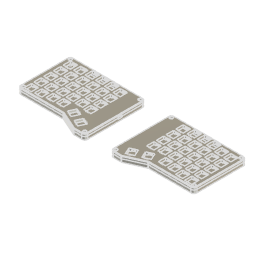
Dos60S (Autodesk Fusion 360 design; units mm, degrees)
Autodesk Fusion 360 part; units mm, degrees
(part 1 of 4)
sketch "Switch_Holes" plane through (0, 0, 0) normal (0, 0, 1) x (1, 0, 0) in component "Plate_Left"
  line L0 (2.5, -8.35) -> (16.5, -8.35)
  line L1 (16.5, -8.35) -> (16.5, -22.35)
  line L2 (16.5, -22.35) -> (2.5, -22.35)
  line L3 (2.5, -22.35) -> (2.5, -8.35)
  line L4 (2.5, -8.35) -> (16.5, -22.35) construction
  line L5 (2.5, -41.4) -> (2.5, -27.4)
  line L6 (2.5, -27.4) -> (16.5, -27.4)
  line L7 (2.5, -27.4) -> (16.5, -41.4) construction
  line L8 (16.5, -41.4) -> (2.5, -41.4)
  line L9 (16.5, -27.4) -> (16.5, -41.4)
  line L10 (9.5, -15.35) -> (9.5, -34.4) construction
  line L11 (16.5, -60.45) -> (2.5, -60.45)
  line L12 (16.5, -46.45) -> (16.5, -60.45)
  line L13 (2.5, -46.45) -> (16.5, -60.45) construction
  line L14 (2.5, -60.45) -> (2.5, -46.45)
  line L15 (2.5, -46.45) -> (16.5, -46.45)
  line L16 (16.5, -79.5) -> (2.5, -79.5)
  line L17 (16.5, -65.5) -> (16.5, -79.5)
  line L18 (2.5, -65.5) -> (16.5, -79.5) construction
  line L19 (2.5, -79.5) -> (2.5, -65.5)
  line L20 (2.5, -65.5) -> (16.5, -65.5)
  line L21 (16.5, -98.55) -> (2.5, -98.55)
  line L22 (16.5, -84.55) -> (16.5, -98.55)
  line L23 (2.5, -84.55) -> (16.5, -98.55) construction
  line L24 (2.5, -98.55) -> (2.5, -84.55)
  line L25 (2.5, -84.55) -> (16.5, -84.55)
  line L26 (9.5, -34.4) -> (9.5, -53.45) construction
  line L27 (9.5, -53.45) -> (9.5, -72.5) construction
  line L28 (9.5, -72.5) -> (9.5, -91.55) construction
  line L29 (35.55, -45.31) -> (35.55, -59.31)
  line L30 (28.55, -71.36) -> (28.55, -90.41) construction
  line L31 (21.55, -64.36) -> (35.55, -78.36) construction
  line L32 (28.55, -33.26) -> (28.55, -52.31) construction
  line L33 (35.55, -78.36) -> (21.55, -78.36)
  line L34 (28.55, -52.31) -> (28.55, -71.36) construction
  line L35 (21.55, -64.36) -> (35.55, -64.36)
  line L36 (21.55, -83.41) -> (35.55, -97.41) construction
  line L37 (35.55, -59.31) -> (21.55, -59.31)
  line L38 (21.55, -78.36) -> (21.55, -64.36)
  line L39 (35.55, -26.26) -> (35.55, -40.26)
  line L40 (35.55, -7.21) -> (35.55, -21.21)
  line L41 (28.55, -14.21) -> (28.55, -33.26) construction
  line L42 (21.55, -21.21) -> (21.55, -7.21)
  line L43 (21.55, -7.21) -> (35.55, -21.21) construction
  line L44 (35.55, -64.36) -> (35.55, -78.36)
  line L45 (35.55, -21.21) -> (21.55, -21.21)
  line L46 (35.55, -40.26) -> (21.55, -40.26)
  line L47 (21.55, -26.26) -> (35.55, -26.26)
  line L48 (21.55, -97.41) -> (21.55, -83.41)
  line L49 (21.55, -40.26) -> (21.55, -26.26)
  line L50 (21.55, -7.21) -> (35.55, -7.21)
  line L51 (21.55, -83.41) -> (35.55, -83.41)
  line L52 (35.55, -97.41) -> (21.55, -97.41)
  line L53 (21.55, -26.26) -> (35.55, -40.26) construction
  line L54 (21.55, -45.31) -> (35.55, -45.31)
  line L55 (21.55, -59.31) -> (21.55, -45.31)
  line L56 (35.55, -83.41) -> (35.55, -97.41)
  line L57 (21.55, -45.31) -> (35.55, -59.31) construction
  line L58 (54.6, -41.69) -> (54.6, -55.69)
  line L59 (47.6, -67.74) -> (47.6, -86.79) construction
  line L60 (40.6, -60.74) -> (54.6, -74.74) construction
  line L61 (47.6, -29.64) -> (47.6, -48.69) construction
  line L62 (54.6, -74.74) -> (40.6, -74.74)
  line L63 (47.6, -48.69) -> (47.6, -67.74) construction
  line L64 (40.6, -60.74) -> (54.6, -60.74)
  line L65 (40.6, -79.79) -> (54.6, -93.79) construction
  line L66 (54.6, -55.69) -> (40.6, -55.69)
  line L67 (40.6, -74.74) -> (40.6, -60.74)
  line L68 (54.6, -22.64) -> (54.6, -36.64)
  line L69 (54.6, -3.59) -> (54.6, -17.59)
  line L70 (47.6, -10.59) -> (47.6, -29.64) construction
  line L71 (40.6, -17.59) -> (40.6, -3.59)
  line L72 (40.6, -3.59) -> (54.6, -17.59) construction
  line L73 (54.6, -60.74) -> (54.6, -74.74)
  line L74 (54.6, -17.59) -> (40.6, -17.59)
  line L75 (54.6, -36.64) -> (40.6, -36.64)
  line L76 (40.6, -22.64) -> (54.6, -22.64)
  line L77 (40.6, -93.79) -> (40.6, -79.79)
  line L78 (40.6, -36.64) -> (40.6, -22.64)
  line L79 (40.6, -3.59) -> (54.6, -3.59)
  line L80 (40.6, -79.79) -> (54.6, -79.79)
  line L81 (54.6, -93.79) -> (40.6, -93.79)
  line L82 (40.6, -22.64) -> (54.6, -36.64) construction
  line L83 (40.6, -41.69) -> (54.6, -41.69)
  line L84 (40.6, -55.69) -> (40.6, -41.69)
  line L85 (54.6, -79.79) -> (54.6, -93.79)
  line L86 (40.6, -41.69) -> (54.6, -55.69) construction
  line L87 (73.65, -40.6) -> (73.65, -54.6)
  line L88 (66.65, -66.65) -> (66.65, -85.7) construction
  line L89 (59.65, -59.65) -> (73.65, -73.65) construction
  line L90 (66.65, -28.55) -> (66.65, -47.6) construction
  line L91 (73.65, -73.65) -> (59.65, -73.65)
  line L92 (66.65, -47.6) -> (66.65, -66.65) construction
  line L93 (59.65, -59.65) -> (73.65, -59.65)
  line L94 (59.65, -78.7) -> (73.65, -92.7) construction
  line L95 (73.65, -54.6) -> (59.65, -54.6)
  line L96 (59.65, -73.65) -> (59.65, -59.65)
  line L97 (73.65, -21.55) -> (73.65, -35.55)
  line L98 (73.65, -2.5) -> (73.65, -16.5)
  line L99 (66.65, -9.5) -> (66.65, -28.55) construction
  line L100 (59.65, -16.5) -> (59.65, -2.5)
  line L101 (59.65, -2.5) -> (73.65, -16.5) construction
  line L102 (73.65, -59.65) -> (73.65, -73.65)
  line L103 (73.65, -16.5) -> (59.65, -16.5)
  line L104 (73.65, -35.55) -> (59.65, -35.55)
  line L105 (59.65, -21.55) -> (73.65, -21.55)
  line L106 (59.65, -92.7) -> (59.65, -78.7)
  line L107 (59.65, -35.55) -> (59.65, -21.55)
  line L108 (59.65, -2.5) -> (73.65, -2.5)
  line L109 (59.65, -78.7) -> (73.65, -78.7)
  line L110 (73.65, -92.7) -> (59.65, -92.7)
  line L111 (59.65, -21.55) -> (73.65, -35.55) construction
  line L112 (59.65, -40.6) -> (73.65, -40.6)
  line L113 (59.65, -54.6) -> (59.65, -40.6)
  line L114 (73.65, -78.7) -> (73.65, -92.7)
  line L115 (59.65, -40.6) -> (73.65, -54.6) construction
  line L116 (92.7, -41.69) -> (92.7, -55.69)
  line L117 (78.7, -60.74) -> (92.7, -74.74) construction
  line L118 (85.7, -29.64) -> (85.7, -48.69) construction
  line L119 (92.7, -74.74) -> (78.7, -74.74)
  line L120 (85.7, -48.69) -> (85.7, -67.74) construction
  line L121 (78.7, -60.74) -> (92.7, -60.74)
  line L122 (92.7, -55.69) -> (78.7, -55.69)
  line L123 (78.7, -74.74) -> (78.7, -60.74)
  line L124 (92.7, -22.64) -> (92.7, -36.64)
  line L125 (92.7, -3.59) -> (92.7, -17.59)
  line L126 (85.7, -10.59) -> (85.7, -29.64) construction
  line L127 (78.7, -17.59) -> (78.7, -3.59)
  line L128 (78.7, -3.59) -> (92.7, -17.59) construction
  line L129 (92.7, -60.74) -> (92.7, -74.74)
  line L130 (92.7, -17.59) -> (78.7, -17.59)
  line L131 (92.7, -36.64) -> (78.7, -36.64)
  line L132 (78.7, -22.64) -> (92.7, -22.64)
  line L133 (78.7, -36.64) -> (78.7, -22.64)
  line L134 (78.7, -3.59) -> (92.7, -3.59)
  line L135 (78.7, -22.64) -> (92.7, -36.64) construction
  line L136 (78.7, -41.69) -> (92.7, -41.69)
  line L137 (78.7, -55.69) -> (78.7, -41.69)
  line L138 (78.7, -41.69) -> (92.7, -55.69) construction
  line L139 (111.75, -44.35) -> (111.75, -58.35)
  line L140 (97.75, -63.4) -> (111.75, -77.4) construction
  line L141 (104.75, -32.3) -> (104.75, -51.35) construction
  line L142 (111.75, -77.4) -> (97.75, -77.4)
  line L143 (104.75, -51.35) -> (104.75, -70.4) construction
  line L144 (97.75, -63.4) -> (111.75, -63.4)
  line L145 (111.75, -58.35) -> (97.75, -58.35)
  line L146 (97.75, -77.4) -> (97.75, -63.4)
  line L147 (111.75, -25.3) -> (111.75, -39.3)
  line L148 (111.75, -6.25) -> (111.75, -20.25)
  line L149 (104.75, -13.25) -> (104.75, -32.3) construction
  line L150 (97.75, -20.25) -> (97.75, -6.25)
  line L151 (97.75, -6.25) -> (111.75, -20.25) construction
  line L152 (111.75, -63.4) -> (111.75, -77.4)
  line L153 (111.75, -20.25) -> (97.75, -20.25)
  line L154 (111.75, -39.3) -> (97.75, -39.3)
  line L155 (97.75, -25.3) -> (111.75, -25.3)
  line L156 (97.75, -39.3) -> (97.75, -25.3)
  line L157 (97.75, -6.25) -> (111.75, -6.25)
  line L158 (97.75, -25.3) -> (111.75, -39.3) construction
  line L159 (97.75, -44.35) -> (111.75, -44.35)
  line L160 (97.75, -58.35) -> (97.75, -44.35)
  line L161 (97.75, -44.35) -> (111.75, -58.35) construction
  line L162 (97.2384, -101.5355) -> (84.4545, -95.8284)
  line L163 (84.4545, -95.8284) -> (90.1617, -83.0445)
  line L164 (90.1617, -83.0445) -> (102.9456, -88.7516)
  line L165 (102.9456, -88.7516) -> (97.2384, -101.5355)
  line L166 (97.2384, -101.5355) -> (90.1617, -83.0445) construction
  line L167 (84.4545, -95.8284) -> (102.9456, -88.7516) construction
  line L168 (119.7884, -111.1955) -> (107.0045, -105.4884)
  line L169 (107.0045, -105.4884) -> (112.7117, -92.7045)
  line L170 (112.7117, -92.7045) -> (125.4956, -98.4116)
  line L171 (125.4956, -98.4116) -> (119.7884, -111.1955)
  line L172 (119.7884, -111.1955) -> (112.7117, -92.7045) construction
  line L173 (107.0045, -105.4884) -> (125.4956, -98.4116) construction
  line L174 (76.15, -95.2) -> (57.15, -95.2) construction
  line L175 (57.15, -95.2) -> (57.15, -76.2) construction
  line L176 (57.15, -76.2) -> (76.15, -76.2) construction
  line L177 (76.15, -76.2) -> (76.15, -95.2) construction
  line L178 (76.15, -95.2) -> (57.15, -76.2) construction
  line L179 (57.15, -95.2) -> (76.15, -76.2) construction
  line L180 (102.8395, -106.7739) -> (76.8151, -95.1557) construction
  line L181 (76.8151, -95.1557) -> (84.5606, -77.8061) construction
  line L182 (84.5606, -77.8061) -> (110.5849, -89.4243) construction
  line L183 (110.5849, -89.4243) -> (102.8395, -106.7739) construction
  line L184 (102.8395, -106.7739) -> (84.5606, -77.8061) construction
  line L185 (76.8151, -95.1557) -> (110.5849, -89.4243) construction
  line L186 (119.1157, -118.8349) -> (101.7661, -111.0895) construction
  line L187 (101.7661, -111.0895) -> (113.3843, -85.0651) construction
  line L188 (113.3843, -85.0651) -> (130.7339, -92.8105) construction
  line L189 (130.7339, -92.8105) -> (119.1157, -118.8349) construction
  line L190 (119.1157, -118.8349) -> (113.3843, -85.0651) construction
  line L191 (101.7661, -111.0895) -> (130.7339, -92.8105) construction
  line L192 (95.2, -77.24) -> (76.2, -77.24) construction
  line L193 (76.2, -77.24) -> (76.2, -58.24) construction
  line L194 (76.2, -58.24) -> (95.2, -58.24) construction
  line L195 (95.2, -58.24) -> (95.2, -77.24) construction
  line L196 (95.2, -77.24) -> (76.2, -58.24) construction
  line L197 (76.2, -77.24) -> (95.2, -58.24) construction
  line L198 (114.25, -79.9) -> (95.25, -79.9) construction
  line L199 (95.25, -79.9) -> (95.25, -60.9) construction
  line L200 (95.25, -60.9) -> (114.25, -60.9) construction
  line L201 (114.25, -60.9) -> (114.25, -79.9) construction
  line L202 (114.25, -79.9) -> (95.25, -60.9) construction
  line L203 (95.25, -79.9) -> (114.25, -60.9) construction
  line L204 (76.15, -76.15) -> (57.15, -76.15) construction
  line L205 (57.15, -76.15) -> (57.15, -57.15) construction
  line L206 (57.15, -57.15) -> (76.15, -57.15) construction
  line L207 (76.15, -57.15) -> (76.15, -76.15) construction
  line L208 (76.15, -76.15) -> (57.15, -57.15) construction
  line L209 (57.15, -76.15) -> (76.15, -57.15) construction
  line L210 (112.7117, -92.7045) -> (113.3843, -85.0651) construction
  line L211 (125.4956, -98.4116) -> (130.7339, -92.8105) construction
  line L212 (119.1157, -118.8349) -> (119.7884, -111.1955) construction
  line L213 (101.7661, -111.0895) -> (107.0045, -105.4884) construction
  line L214 (84.5606, -77.8061) -> (90.1617, -83.0445) construction
  line L215 (76.8151, -95.1557) -> (84.4545, -95.8284) construction
  line L216 (110.5849, -89.4243) -> (102.9456, -88.7516) construction
  line L217 (102.8395, -106.7739) -> (97.2384, -101.5355) construction
  line L218 (102.9456, -88.7516) -> (112.7117, -92.7045) construction
  line L219 (97.2384, -101.5355) -> (107.0045, -105.4884) construction
  line L220 (19, -24.85) -> (0, -24.85) construction
  line L221 (0, -24.85) -> (0, -5.85) construction
  line L222 (0, -5.85) -> (19, -5.85) construction
  line L223 (19, -5.85) -> (19, -24.85) construction
  line L224 (19, -24.85) -> (0, -5.85) construction
  line L225 (0, -24.85) -> (19, -5.85) construction
  line L226 (76.15, -19) -> (57.15, -19) construction
  line L227 (57.15, -19) -> (57.15, 0) construction
  line L228 (57.15, 0) -> (76.15, 0) construction
  line L229 (76.15, 0) -> (76.15, -19) construction
  line L230 (76.15, -19) -> (57.15, 0) construction
  line L231 (57.15, -19) -> (76.15, 0) construction
  line L232 (0, 0) -> (128, 0) construction
  line L233 (0, 0) -> (0, -128) construction
  line L234 (0, -101.05) -> (19, -101.05) construction
  line L235 (19, -101.05) -> (19, -82.05) construction
  line L236 (19, -82.05) -> (0, -82.05) construction
  line L237 (0, -82.05) -> (0, -101.05) construction
  line L238 (0, -101.05) -> (19, -82.05) construction
  line L239 (19, -101.05) -> (0, -82.05) construction
  line L240 (114.25, -22.75) -> (95.25, -22.75) construction
  line L241 (95.25, -22.75) -> (95.25, -3.75) construction
  line L242 (95.25, -3.75) -> (114.25, -3.75) construction
  line L243 (114.25, -3.75) -> (114.25, -22.75) construction
  line L244 (114.25, -22.75) -> (95.25, -3.75) construction
  line L245 (95.25, -22.75) -> (114.25, -3.75) construction
  point P0 (9.5, -15.35)
  point P1 (9.5, -34.4)
  point P2 (9.5, -53.45)
  point P3 (9.5, -53.45)
  point P4 (9.5, -72.5)
  point P5 (9.5, -72.5)
  point P6 (9.5, -91.55)
  point P7 (9.5, -91.55)
  point P8 (28.55, -52.31)
  point P9 (28.55, -52.31)
  point P10 (28.55, -90.41)
  point P11 (28.55, -90.41)
  point P12 (28.55, -33.26)
  point P13 (28.55, -71.36)
  point P14 (28.55, -71.36)
  point P15 (28.55, -14.21)
  point P16 (47.6, -48.69)
  point P17 (47.6, -48.69)
  point P18 (47.6, -86.79)
  point P19 (47.6, -86.79)
  point P20 (47.6, -29.64)
  point P21 (47.6, -67.74)
  point P22 (47.6, -67.74)
  point P23 (47.6, -10.59)
  point P24 (66.65, -47.6)
  point P25 (66.65, -47.6)
  point P26 (66.65, -85.7)
  point P27 (66.65, -85.7)
  point P28 (66.65, -28.55)
  point P29 (66.65, -66.65)
  point P30 (66.65, -66.65)
  point P31 (66.65, -9.5)
  point P32 (85.7, -48.69)
  point P33 (85.7, -48.69)
  point P34 (93.7, -92.29)
  point P35 (85.7, -29.64)
  point P36 (85.7, -67.74)
  point P37 (85.7, -67.74)
  point P38 (85.7, -10.59)
  point P39 (104.75, -51.35)
  point P40 (104.75, -51.35)
  point P41 (104.75, -32.3)
  point P42 (104.75, -70.4)
  point P43 (104.75, -70.4)
  point P44 (104.75, -13.25)
  point P45 (9.5, -8.35)
  point P46 (28.55, -7.21)
  point P47 (47.6, -3.59)
  point P48 (66.65, -2.5)
  point P49 (85.7, -3.59)
  point P50 (104.75, -6.25)
  point P51 (93.7, -92.29)
  point P52 (116.25, -101.95)
  point P53 (66.65, -85.7)
  point P54 (93.7, -92.29)
  point P55 (116.25, -101.95)
  point P56 (85.7, -67.74)
  point P57 (104.75, -70.4)
  point P58 (66.65, -66.65)
  point P59 (9.5, -15.35)
  point P60 (66.65, -9.5)
  point P61 (2.5, -15.35)
  point P62 (9.5, -91.55)
  point P63 (104.75, -13.25)
  dimension "d47" = 14
  dimension "d48" = 14
  dimension "d49" = 14
  dimension "d50" = 14
  dimension "d51" = 19.05
  dimension "d52" = 14
  dimension "d53" = 14
  dimension "d54" = 14
  dimension "d55" = 14
  dimension "d56" = 14
  dimension "d57" = 14
  dimension "d58" = 19.05
  dimension "d59" = 19.05
  dimension "d60" = 19.05
  dimension "d61" = 14
  dimension "d62" = 14
  dimension "d63" = 14
  dimension "d64" = 14
  dimension "d65" = 19.05
  dimension "d66" = 14
  dimension "d67" = 14
  dimension "d68" = 14
  dimension "d69" = 14
  dimension "d70" = 14
  dimension "d71" = 14
  dimension "d72" = 19.05
  dimension "d73" = 19.05
  dimension "d74" = 19.05
  dimension "d75" = 14
  dimension "d76" = 14
  dimension "d77" = 14
  dimension "d78" = 14
  dimension "d79" = 19.05
  dimension "d80" = 14
  dimension "d81" = 14
  dimension "d82" = 14
  dimension "d83" = 14
  dimension "d84" = 14
  dimension "d85" = 14
  dimension "d86" = 19.05
  dimension "d87" = 19.05
  dimension "d88" = 19.05
  dimension "d89" = 14
  dimension "d90" = 14
  dimension "d91" = 14
  dimension "d92" = 14
  dimension "d93" = 19.05
  dimension "d94" = 14
  dimension "d95" = 14
  dimension "d96" = 14
  dimension "d97" = 14
  dimension "d98" = 14
  dimension "d99" = 14
  dimension "d100" = 19.05
  dimension "d101" = 19.05
  dimension "d102" = 19.05
  dimension "d103" = 14
  dimension "d104" = 14
  dimension "d105" = 14
  dimension "d106" = 14
  dimension "d107" = 19.05
  dimension "d108" = 14
  dimension "d109" = 14
  dimension "d110" = 14
  dimension "d111" = 14
  dimension "d114" = 19.05
  dimension "d115" = 19.05
  dimension "d117" = 14
  dimension "d118" = 14
  dimension "d119" = 14
  dimension "d120" = 14
  dimension "d121" = 19.05
  dimension "d122" = 14
  dimension "d123" = 14
  dimension "d124" = 14
  dimension "d125" = 14
  dimension "d128" = 19.05
  dimension "d129" = 19.05
  dimension "d149" = 19.05
  dimension "d150" = 19.05
  dimension "d151" = 19.05
  dimension "d156" = 27.05
  dimension "d160" = 14
  dimension "d161" = 14
  dimension "d163" = 24.55
  dimension "d164" = 14
  dimension "d165" = 14
  dimension "d166" = 22.55
  dimension "d168" = 31.55
  dimension "d173" = 19
  dimension "d174" = 19
  dimension "d175" = 28.5
  dimension "d176" = 19
  dimension "d177" = 19
  dimension "d178" = 28.5
  dimension "d179" = 19
  dimension "d180" = 19
  dimension "d181" = 19
  dimension "d182" = 19
  dimension "d183" = 19
  dimension "d184" = 19
  dimension "d185" = 19
  dimension "d186" = 19
  dimension "d187" = 19
  dimension "d188" = 19
  dimension "d190" = 8.35
  dimension "d191" = 7.21
  dimension "d192" = 3.59
  dimension "d194" = 3.59
  dimension "d195" = 6.25
  dimension "d196" = 9.5
  dimension "d204" = 19.05
  dimension "d205" = 19.05
  dimension "d208" = 19
  dimension "d209" = 19
  dimension "d210" = 19
  dimension "d211" = 19
  constraint horizontal L0
  constraint vertical L1
  constraint horizontal L2
  constraint vertical L3
  constraint midpoint L4 P59
  constraint horizontal L6
  constraint vertical L9
  constraint horizontal L8
  constraint vertical L5
  constraint midpoint P1 L7
  constraint coincident P59 P0
  constraint coincident P1 L10.end
  constraint perpendicular L6 L10
  constraint horizontal L15
  constraint vertical L12
  constraint horizontal L11
  constraint vertical L14
  constraint midpoint P3 L13
  constraint coincident P3 P2
  constraint horizontal L20
  constraint vertical L17
  constraint horizontal L16
  constraint vertical L19
  constraint midpoint P5 L18
  constraint coincident P5 P4
  constraint horizontal L25
  constraint vertical L22
  constraint horizontal L21
  constraint vertical L24
  constraint midpoint P62 L23
  constraint coincident P62 P7
  constraint perpendicular L15 L26
  constraint parallel L26 L27
  constraint perpendicular L25 L28
  constraint horizontal L50
  constraint vertical L40
  constraint horizontal L45
  constraint vertical L42
  constraint midpoint P15 L43
  constraint horizontal L47
  constraint vertical L39
  constraint horizontal L46
  constraint vertical L49
  constraint midpoint P12 L53
  constraint coincident P15 L41.start
  constraint coincident P12 L32.start
  constraint perpendicular L41 L47
  constraint horizontal L54
  constraint vertical L29
  constraint horizontal L37
  constraint vertical L55
  constraint midpoint P9 L57
  constraint coincident P9 P8
  constraint horizontal L35
  constraint vertical L44
  constraint horizontal L33
  constraint vertical L38
  constraint midpoint P14 L31
  constraint coincident P14 P13
  constraint horizontal L51
  constraint vertical L56
  constraint horizontal L52
  constraint vertical L48
  constraint midpoint P11 L36
  constraint coincident P11 P10
  constraint perpendicular L32 L54
  constraint parallel L32 L34
  constraint perpendicular L30 L51
  constraint horizontal L79
  constraint vertical L69
  constraint horizontal L74
  constraint vertical L71
  constraint midpoint P23 L72
  constraint horizontal L76
  constraint vertical L68
  constraint horizontal L75
  constraint vertical L78
  constraint midpoint P20 L82
  constraint coincident P23 L70.start
  constraint coincident P20 L61.start
  constraint perpendicular L70 L76
  constraint horizontal L83
  constraint vertical L58
  constraint horizontal L66
  constraint vertical L84
  constraint midpoint P17 L86
  constraint coincident P17 P16
  constraint horizontal L64
  constraint vertical L73
  constraint horizontal L62
  constraint vertical L67
  constraint midpoint P22 L60
  constraint coincident P22 P21
  constraint horizontal L80
  constraint vertical L85
  constraint horizontal L81
  constraint vertical L77
  constraint midpoint P19 L65
  constraint coincident P19 P18
  constraint perpendicular L61 L83
  constraint parallel L61 L63
  constraint perpendicular L59 L80
  constraint horizontal L108
  constraint vertical L98
  constraint horizontal L103
  constraint vertical L100
  constraint midpoint P60 L101
  constraint horizontal L105
  constraint vertical L97
  constraint horizontal L104
  constraint vertical L107
  constraint midpoint P28 L111
  constraint coincident P60 P31
  constraint coincident P28 L90.start
  constraint perpendicular L99 L105
  constraint horizontal L112
  constraint vertical L87
  constraint horizontal L95
  constraint vertical L113
  constraint midpoint P25 L115
  constraint coincident P25 P24
  constraint horizontal L93
  constraint vertical L102
  constraint horizontal L91
  constraint vertical L96
  constraint midpoint P58 L89
  constraint coincident P58 P30
  constraint horizontal L109
  constraint vertical L114
  constraint horizontal L110
  constraint vertical L106
  constraint midpoint P53 L94
  constraint coincident P53 P27
  constraint perpendicular L90 L112
  constraint parallel L90 L92
  constraint perpendicular L88 L109
  constraint horizontal L134
  constraint vertical L125
  constraint horizontal L130
  constraint vertical L127
  constraint midpoint P38 L128
  constraint horizontal L132
  constraint vertical L124
  constraint horizontal L131
  constraint vertical L133
  constraint midpoint P35 L135
  constraint coincident P38 L126.start
  constraint coincident P35 L118.start
  constraint perpendicular L126 L132
  constraint horizontal L136
  constraint vertical L116
  constraint horizontal L122
  constraint vertical L137
  constraint midpoint P33 L138
  constraint coincident P33 P32
  constraint horizontal L121
  constraint vertical L129
  constraint horizontal L119
  constraint vertical L123
  constraint midpoint P56 L117
  constraint coincident P56 P37
  constraint perpendicular L118 L136
  constraint parallel L118 L120
  constraint horizontal L157
  constraint vertical L148
  constraint horizontal L153
  constraint vertical L150
  constraint midpoint P63 L151
  constraint horizontal L155
  constraint vertical L147
  constraint horizontal L154
  constraint vertical L156
  constraint midpoint P41 L158
  constraint coincident P63 P44
  constraint coincident P41 L141.start
  constraint perpendicular L149 L155
  constraint horizontal L159
  constraint vertical L139
  constraint horizontal L145
  constraint vertical L160
  constraint midpoint P40 L161
  constraint coincident P40 P39
  constraint horizontal L144
  constraint vertical L152
  constraint horizontal L142
  constraint vertical L146
  constraint midpoint P57 L140
  constraint coincident P57 P43
  constraint perpendicular L141 L159
  constraint parallel L141 L143
  constraint midpoint L0 P45
  constraint midpoint L50 P46
  constraint midpoint L79 P47
  constraint midpoint L108 P48
  constraint midpoint L134 P49
  constraint midpoint L157 P50
  constraint perpendicular L162 L163
  constraint parallel L162 L164
  constraint parallel L163 L165
  constraint coincident L166 P54
  constraint coincident L167 P54
  constraint coincident P54 P51
  constraint perpendicular L168 L169
  constraint parallel L168 L170
  constraint parallel L169 L171
  constraint coincident L172 P55
  constraint coincident L173 P55
  constraint horizontal L174
  constraint perpendicular L174 L175
  constraint parallel L174 L176
  constraint parallel L175 L177
  constraint coincident L178 P53
  constraint coincident L179 P53
  constraint perpendicular L180 L181
  constraint parallel L180 L182
  constraint parallel L181 L183
  constraint coincident L184 P54
  constraint coincident L185 P54
  constraint perpendicular L186 L187
  constraint parallel L186 L188
  constraint parallel L187 L189
  constraint coincident L190 P55
  constraint coincident L191 P55
  constraint coincident P55 P52
  constraint horizontal L192
  constraint perpendicular L192 L193
  constraint parallel L192 L194
  constraint parallel L193 L195
  constraint coincident L196 P56
  constraint coincident L197 P56
  constraint horizontal L198
  constraint perpendicular L198 L199
  constraint parallel L198 L200
  constraint parallel L199 L201
  constraint coincident L202 P57
  constraint coincident L203 P57
  constraint horizontal L204
  constraint perpendicular L204 L205
  constraint parallel L204 L206
  constraint parallel L205 L207
  constraint coincident L208 P58
  constraint coincident L209 P58
  constraint equal L210 L211
  constraint equal L216 L217
  constraint equal L218 L219
  constraint horizontal L220
  constraint perpendicular L220 L221
  constraint parallel L220 L222
  constraint parallel L221 L223
  constraint coincident L224 P59
  constraint coincident L225 P59
  constraint horizontal L226
  constraint perpendicular L226 L227
  constraint parallel L226 L228
  constraint parallel L227 L229
  constraint coincident L230 P60
  constraint coincident L231 P60
  constraint horizontal L232
  constraint coincident L232.start L233.start
  constraint vertical L233
  constraint midpoint L3 P61
  constraint horizontal L234
  constraint perpendicular L234 L235
  constraint parallel L234 L236
  constraint parallel L235 L237
  constraint coincident L238 P62
  constraint coincident L239 P62
  constraint horizontal L240
  constraint perpendicular L240 L241
  constraint parallel L240 L242
  constraint parallel L241 L243
  constraint coincident L244 P63
  constraint coincident L245 P63
  measures "d47" distance of L0.start L0.end
  measures "d48" distance of L0.start L2.end
  measures "d49" distance of L6.end L5.end
  measures "d50" distance of L5.start L5.end
  measures "d51" distance of P59 P1
  measures "d52" distance of L12.start L13.start
  measures "d53" distance of L11.end L13.start
  measures "d54" distance of L17.start L18.start
  measures "d55" distance of L16.end L18.start
  measures "d56" distance of L22.start L23.start
  measures "d57" distance of L21.end L23.start
  measures "d58" distance of P1 P3
  measures "d59" distance of P3 P5
  measures "d60" distance of P5 P62
  measures "d61" distance of L40.start L42.end
  measures "d62" distance of L42.start L42.end
  measures "d63" distance of L39.start L47.start
  measures "d64" distance of L46.end L47.start
  measures "d65" distance of P12 P15
  measures "d66" distance of L29.start L54.start
  measures "d67" distance of L37.end L54.start
  measures "d68" distance of L35.end L31.start
  measures "d69" distance of L31.start L33.end
  measures "d70" distance of L51.end L36.start
  measures "d71" distance of L48.start L36.start
  measures "d72" distance of P9 P12
  measures "d73" distance of P9 P14
  measures "d74" distance of P11 P14
  measures "d75" distance of L69.start L71.end
  measures "d76" distance of L71.start L71.end
  measures "d77" distance of L68.start L76.start
  measures "d78" distance of L75.end L76.start
  measures "d79" distance of P20 P23
  measures "d80" distance of L58.start L83.start
  measures "d81" distance of L66.end L83.start
  measures "d82" distance of L64.end L60.start
  measures "d83" distance of L60.start L62.end
  measures "d84" distance of L80.end L65.start
  measures "d85" distance of L77.start L65.start
  measures "d86" distance of P17 P20
  measures "d87" distance of P17 P22
  measures "d88" distance of P19 P22
  measures "d89" distance of L98.start L100.end
  measures "d90" distance of L100.start L100.end
  measures "d91" distance of L97.start L105.start
  measures "d92" distance of L104.end L105.start
  measures "d93" distance of P28 P60
  measures "d94" distance of L87.start L112.start
  measures "d95" distance of L95.end L112.start
  measures "d96" distance of L93.end L89.start
  measures "d97" distance of L89.start L91.end
  measures "d98" distance of L109.end L94.start
  measures "d99" distance of L106.start L94.start
  measures "d100" distance of P25 P28
  measures "d101" distance of P25 P58
  measures "d102" distance of P53 P58
  measures "d103" distance of L125.start L127.end
  measures "d104" distance of L127.start L127.end
  measures "d105" distance of L124.start L132.start
  measures "d106" distance of L131.end L132.start
  measures "d107" distance of P35 P38
  measures "d108" distance of L116.start L136.start
  measures "d109" distance of L122.end L136.start
  measures "d110" distance of L121.end L117.start
  measures "d111" distance of L117.start L119.end
  measures "d114" distance of P33 P35
  measures "d115" distance of P33 P56
  measures "d117" distance of L148.start L150.end
  measures "d118" distance of L150.start L150.end
  measures "d119" distance of L147.start L155.start
  measures "d120" distance of L154.end L155.start
  measures "d121" distance of P41 P63
  measures "d122" distance of L139.start L159.start
  measures "d123" distance of L145.end L159.start
  measures "d124" distance of L144.end L140.start
  measures "d125" distance of L140.start L142.end
  measures "d128" distance of P40 P41
  measures "d129" distance of P40 P57
  measures "d149" horizontal distance of P62 P11
  measures "d150" horizontal distance of P11 P19
  measures "d151" horizontal distance of P19 P53
  measures "d156" horizontal distance of P53 P54
  measures "d160" distance of L163.end L164.end
  measures "d161" distance of L162.end L163.end
  measures "d163" vertical distance of P56 P54
  measures "d164" distance of L169.end L170.end
  measures "d165" distance of L168.end L169.end
  measures "d166" horizontal distance of P54 P55
  measures "d168" vertical distance of P57 P55
  measures "d173" distance of L175.end L176.end
  measures "d174" distance of L174.end L175.end
  measures "d175" distance of L181.end L182.end
  measures "d176" distance of L180.end L181.end
  measures "d177" distance of L187.end L188.end
  measures "d178" distance of L186.end L187.end
  measures "d179" distance of L193.end L194.end
  measures "d180" distance of L192.end L193.end
  measures "d181" distance of L199.end L200.end
  measures "d182" distance of L198.end L199.end
  measures "d183" distance of L205.end L206.end
  measures "d184" distance of L204.end L205.end
  measures "d185" distance of L221.end L222.end
  measures "d186" distance of L220.end L221.end
  measures "d187" distance of L227.end L228.end
  measures "d188" distance of L226.end L227.end
  measures "d190" distance of P45 L232
  measures "d191" distance of P46 L232
  measures "d192" distance of P47 L232
  measures "d194" distance of P49 L232
  measures "d195" distance of P50 L232
  measures "d196" distance of P60 L232
  measures "d204" horizontal distance of P38 P60
  measures "d205" horizontal distance of P38 P63
  measures "d208" distance of L235.end L236.end
  measures "d209" distance of L234.end L235.end
  measures "d210" distance of L241.end L242.end
  measures "d211" distance of L240.end L241.end
sketch "General_Case_Outline" plane through (0, 0, 0) normal (0, 0, 1) x (1, 0, 0) in component "Plate_Left"
  line L0 (0, -0.0028) -> (135.25, -0.0028)
  line L1 (141.25, -6.0028) -> (141.25, -113.172)
  line L2 (-6, -97) -> (-6, -6.0028)
  arc A0 (0, -0.0028) -> (-6, -6.0028) centre (0, -6.0028) ccw
  arc A1 (141.25, -6.0028) -> (135.25, -0.0028) centre (135.25, -6.0028) ccw
  arc A2 (135.25, -119.172) -> (141.25, -113.172) centre (135.25, -113.172) ccw
  arc A3 (-6, -97) -> (0, -103) centre (0, -97) ccw
  line L3 (0, -103) -> (82.8467, -103)
  line L4 (135.25, -119.172) -> (120.1238, -119.172)
  line L5 (119.3123, -118.9999) -> (83.6581, -103.172)
  arc A4 (83.6581, -103.172) -> (82.8467, -103) centre (82.8467, -105) ccw
  arc A5 (119.3123, -118.9999) -> (120.1238, -119.172) centre (120.1238, -117.172) ccw
  line L6 (111.75, -25.3) -> (111.75, -39.3)
  line L7 (2.5, -41.4) -> (2.5, -27.4)
  dimension "d207" = 6
  dimension "d212" = 2
  dimension "d213" = 2
  dimension "d214" = 29.5
  dimension "d481" = 8.5
  constraint horizontal L0
  constraint vertical L1
  constraint vertical L2
  constraint tangent L0 A0
  constraint tangent L2 A0
  constraint tangent L0 A1
  constraint tangent L1 A1
  constraint equal A0 A1
  constraint tangent L1 A2
  constraint equal A0 A2
  constraint tangent L2 A3
  constraint equal A0 A3
  constraint tangent A3 L3
  constraint perpendicular L2 L3
  constraint tangent A2 L4
  constraint horizontal L4
  constraint tangent L3 A4
  constraint tangent L5 A4
  constraint tangent L5 A5
  constraint tangent L4 A5
  measures "d207" radius of A0
  measures "d212" radius of A4
  measures "d213" radius of A5
  measures "d214" distance of L1 L6
  measures "d481" distance of L2 L7
extrude "Extrude4" add sketch "General_Case_Outline" along normal blind 5 makes body 1 in component "Plate_Left"
extrude "Extrude5" cut sketch "Switch_Holes" along normal through all bodies 1 in component "Plate_Left"